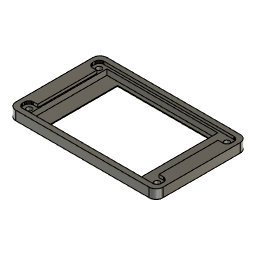
LCD_Skirt_Assembly (Autodesk Fusion 360 archive; units mm, degrees)
design "LCD_Face_Plate"
Autodesk Fusion 360 part; units mm, degrees
sketch "Adafruit PiTFT+ 3.2in-Edge_Cuts" plane through (0, 0, 0) normal (0, 0, 1) x (1, 0, 0)
  line L0 (-48.5948, 26.5683) -> (-48.3621, 27.006)
  line L1 (-48.5898, 23.3269) -> (-48.7364, 23.8005)
  line L2 (-48.74, 26.0892) -> (-48.5967, 26.5637)
  line L3 (-48.7365, 23.8008) -> (-48.7369, 23.803)
  line L4 (-48.3607, 27.0081) -> (-48.3594, 27.01)
  line L5 (-48.7894, 25.5898) -> (-48.7893, 25.591)
  line L6 (-48.7374, 23.8052) -> (-48.7892, 24.2983)
  line L7 (-48.7892, 24.2983) -> (-48.7892, 24.2986)
  line L8 (-48.0461, 27.3942) -> (-48.0461, 27.3942)
  line L9 (-46.7399, 28.1011) -> (-46.7378, 28.1016)
  line L10 (-47.2161, 27.954) -> (-46.7425, 28.1006)
  line L11 (46.7277, 28.1051) -> (46.73, 28.1046)
  line L12 (46.7274, 28.1051) -> (46.7277, 28.1051)
  line L13 (-46.2433, 28.1534) -> (-46.2422, 28.1535)
  line L14 (-46.2422, 28.1535) -> (-46.2257, 28.1536)
  line L15 (-47.6585, 27.7151) -> (-47.6566, 27.7163)
  line L16 (-48.3621, 27.006) -> (-48.3621, 27.006)
  line L17 (-47.6604, 27.7138) -> (-47.6585, 27.7151)
  line L18 (-48.7894, 24.3173) -> (-48.7894, 24.3174)
  line L19 (-46.7422, 28.1007) -> (-46.7399, 28.1011)
  line L20 (46.234, 28.1535) -> (46.7274, 28.1051)
  line L21 (-46.2257, 28.1536) -> (-46.2256, 28.1536)
  line L22 (-47.6607, 27.7136) -> (-47.6604, 27.7138)
  line L23 (47.2092, 27.9599) -> (47.2113, 27.959)
  line L24 (47.2071, 27.9608) -> (47.2092, 27.9599)
  line L25 (-46.7425, 28.1006) -> (-46.7425, 28.1006)
  line L26 (46.2328, 28.1536) -> (46.234, 28.1535)
  line L27 (-48.5966, 26.5641) -> (-48.5957, 26.5662)
  line L28 (46.7322, 28.1042) -> (47.2067, 27.9609)
  line L29 (-48.7409, 26.0847) -> (-48.7404, 26.087)
  line L30 (-48.0461, 27.3942) -> (-48.0459, 27.3944)
  line L31 (-48.7892, 24.2986) -> (-48.7892, 24.2997)
  line L32 (-48.3496, 22.8826) -> (-48.3509, 22.8845)
  line L33 (-48.3621, 27.006) -> (-48.3619, 27.0063)
  line L34 (-48.3594, 27.01) -> (-48.0461, 27.3942)
  line L35 (-48.7409, 26.0844) -> (-48.7409, 26.0847)
  line L36 (-47.2182, 27.9531) -> (-47.2161, 27.954)
  line L37 (-46.2447, 28.1534) -> (-46.2444, 28.1534)
  line L38 (-48.5957, 26.5662) -> (-48.5948, 26.5683)
  line L39 (-46.2444, 28.1534) -> (-46.2433, 28.1534)
  line L40 (-47.6566, 27.7163) -> (-47.2206, 27.9521)
  line L41 (-47.2206, 27.9521) -> (-47.2203, 27.9523)
  line L42 (-48.7364, 23.8005) -> (-48.7365, 23.8008)
  line L43 (-48.7893, 25.591) -> (-48.7893, 25.591)
  line L44 (-48.7893, 24.3008) -> (-48.7894, 24.3173)
  line L45 (-48.7893, 25.591) -> (-48.7409, 26.0844)
  line L46 (-48.3621, 27.006) -> (-48.3621, 27.006)
  line L47 (-48.0461, 27.3942) -> (-48.0461, 27.3942)
  line L48 (-47.2206, 27.9521) -> (-47.2206, 27.9521)
  line L49 (-46.7425, 28.1006) -> (-46.7422, 28.1007)
  line L50 (47.2067, 27.9609) -> (47.2071, 27.9608)
  line L51 (-46.7378, 28.1016) -> (-46.2447, 28.1534)
  line L52 (-48.5967, 26.5637) -> (-48.5966, 26.5641)
  line L53 (-48.3619, 27.0063) -> (-48.3607, 27.0081)
  line L54 (-48.0443, 27.396) -> (-48.0426, 27.3976)
  line L55 (46.73, 28.1046) -> (46.7322, 28.1042)
  line L56 (-48.0459, 27.3944) -> (-48.0443, 27.396)
  line L57 (-48.7369, 23.803) -> (-48.7374, 23.8052)
  line L58 (-48.7894, 24.3174) -> (-48.7894, 25.5898)
  line L59 (-47.6458, 22.1836) -> (-48.03, 22.4969)
  line L60 (-48.7404, 26.087) -> (-48.74, 26.0892)
  line L61 (-48.7892, 24.2997) -> (-48.7893, 24.3008)
  line L62 (48.6039, 23.3435) -> (48.6038, 23.3431)
  line L63 (48.0531, 22.5128) -> (48.0515, 22.5112)
  line L64 (46.7472, 21.8061) -> (46.745, 21.8056)
  line L65 (48.3593, 27.0208) -> (48.5951, 26.5848)
  line L66 (48.7481, 23.8225) -> (48.7476, 23.8202)
  line L67 (48.7964, 25.6089) -> (48.7964, 25.6086)
  line L68 (48.5961, 26.5824) -> (48.597, 26.5803)
  line L69 (46.234, 28.1535) -> (46.234, 28.1535)
  line L70 (48.3666, 22.8972) -> (48.0533, 22.513)
  line L71 (48.7964, 25.6086) -> (48.7964, 25.6075)
  line L72 (48.7472, 23.818) -> (48.6039, 23.3435)
  line L73 (48.3568, 27.0246) -> (48.3581, 27.0227)
  line L74 (48.7965, 25.6064) -> (48.7966, 25.5899)
  line L75 (47.649, 27.7263) -> (47.649, 27.7263)
  line L76 (48.5951, 26.5848) -> (48.5951, 26.5848)
  line L77 (48.7437, 26.1064) -> (48.7441, 26.1041)
  line L78 (48.602, 23.3389) -> (48.3693, 22.9012)
  line L79 (48.0515, 22.5112) -> (48.0498, 22.5096)
  line L80 (48.3691, 22.9009) -> (48.3678, 22.8991)
  line L81 (48.0372, 27.4103) -> (48.0372, 27.4103)
  line L82 (48.7436, 26.1067) -> (48.7437, 26.1064)
  line L83 (48.7446, 26.102) -> (48.7964, 25.6089)
  line L84 (48.039, 27.4085) -> (48.0406, 27.4068)
  line L85 (48.0372, 27.4103) -> (48.0372, 27.4103)
  line L86 (47.2113, 27.959) -> (47.6489, 27.7263)
  line L87 (-47.2206, 27.9521) -> (-47.2206, 27.9521)
  line L88 (48.7965, 24.3162) -> (48.7965, 24.3162)
  line L89 (47.2275, 21.9549) -> (47.2254, 21.9541)
  line L90 (48.7966, 25.5899) -> (48.7966, 25.5898)
  line L91 (48.5951, 26.5848) -> (48.5951, 26.5848)
  line L92 (48.3581, 27.0227) -> (48.3593, 27.0208)
  line L93 (48.6029, 23.341) -> (48.602, 23.3389)
  line L94 (48.0498, 22.5096) -> (47.6679, 22.1936)
  line L95 (-47.2203, 27.9523) -> (-47.2182, 27.9531)
  line L96 (48.0372, 27.4103) -> (48.0374, 27.4101)
  line L97 (48.3693, 22.9012) -> (48.3691, 22.9009)
  line L98 (48.5951, 26.5848) -> (48.5953, 26.5845)
  line L99 (47.6657, 22.1921) -> (47.6638, 22.1909)
  line L100 (47.6676, 22.1934) -> (47.6657, 22.1921)
  line L101 (47.2233, 21.9532) -> (46.7497, 21.8066)
  line L102 (48.7476, 23.8202) -> (48.7472, 23.818)
  line L103 (46.7497, 21.8066) -> (46.7494, 21.8065)
  line L104 (46.7494, 21.8065) -> (46.7472, 21.8061)
  line L105 (47.6679, 22.1936) -> (47.6676, 22.1934)
  line L106 (48.7966, 25.5898) -> (48.7966, 24.3174)
  line L107 (48.3678, 22.8991) -> (48.3666, 22.8972)
  line L108 (47.2254, 21.9541) -> (47.2233, 21.9532)
  line L109 (48.7441, 26.1041) -> (48.7446, 26.102)
  line L110 (48.597, 26.5803) -> (48.7436, 26.1067)
  line L111 (47.653, 27.7236) -> (48.0372, 27.4103)
  line L112 (-48.0426, 27.3976) -> (-47.6607, 27.7136)
  line L113 (47.6493, 27.7261) -> (47.6511, 27.7249)
  line L114 (47.649, 27.7263) -> (47.6493, 27.7261)
  line L115 (48.3566, 27.0249) -> (48.3568, 27.0246)
  line L116 (47.6511, 27.7249) -> (47.653, 27.7236)
  line L117 (48.0406, 27.4068) -> (48.3566, 27.0249)
  line L118 (46.745, 21.8056) -> (46.2519, 21.7538)
  line L119 (48.5953, 26.5845) -> (48.5961, 26.5824)
  line L120 (47.6489, 27.7263) -> (47.649, 27.7263)
  line L121 (48.0374, 27.4101) -> (48.039, 27.4085)
  line L122 (48.7964, 25.6075) -> (48.7965, 25.6064)
  line L123 (-46.2243, -21.8074) -> (-46.2408, -21.8075)
  line L124 (-46.2408, 28.1035) -> (-46.7301, 28.0521)
  line L125 (-47.9965, 22.5341) -> (-47.6161, 22.2239)
  line L126 (48.7966, 24.3174) -> (48.7965, 24.3162)
  line L127 (-47.199, 27.907) -> (-47.6307, 27.6735)
  line L128 (-48.6914, -23.8339) -> (-48.7394, -24.3236)
  line L129 (-48.5495, 26.5469) -> (-48.6914, 26.0771)
  line L130 (-42.5426, -21.8074) -> (-46.2243, -21.8074)
  line L131 (-42.5182, 21.7882) -> (-42.5168, 21.7835)
  line L132 (-47.6161, 22.2239) -> (-47.1827, 21.9935)
  line L133 (-42.5318, 21.8018) -> (-42.5274, 21.7995)
  line L134 (-42.5402, 21.8036) -> (-42.5365, 21.8032)
  line L135 (46.2516, 21.7538) -> (46.2505, 21.7538)
  line L136 (-48.7394, 24.3187) -> (-48.7393, 24.3022)
  line L137 (-47.6307, 27.6735) -> (-48.0089, 27.3607)
  line L138 (-48.6914, 26.0771) -> (-48.7394, 25.5874)
  line L139 (-42.5402, -21.8074) -> (-42.5414, -21.8075)
  line L140 (-42.5402, -21.8074) -> (-42.5402, -21.8074)
  line L141 (-42.5365, 21.8032) -> (-42.5318, 21.8018)
  line L142 (-42.5168, 21.7835) -> (-42.5163, 21.7786)
  line L143 (48.0533, 22.513) -> (48.0531, 22.5128)
  line L144 (-46.7301, -21.8589) -> (-47.199, -22.004)
  line L145 (-46.2243, 28.1036) -> (-46.2408, 28.1035)
  line L146 (-48.3191, -22.9307) -> (-48.5495, -23.3641)
  line L147 (46.2329, 21.7536) -> (46.2328, 21.7536)
  line L148 (-46.2232, 21.8036) -> (-42.5426, 21.8036)
  line L149 (-48.7393, 24.3022) -> (-48.6879, 23.8129)
  line L150 (-48.0089, -22.5503) -> (-48.3191, -22.9307)
  line L151 (42.4466, 21.7536) -> (42.4466, -21.7574)
  line L152 (-42.5205, -21.7964) -> (-42.5236, -21.8002)
  line L153 (48.7481, 23.8228) -> (48.7481, 23.8225)
  line L154 (-42.5365, -21.807) -> (-42.5402, -21.8074)
  line L155 (47.2278, 21.9551) -> (47.2275, 21.9549)
  line L156 (-42.5164, 21.7774) -> (-42.5164, -21.7812)
  line L157 (46.2328, 21.7536) -> (42.4466, 21.7536)
  line L158 (-47.1827, 21.9935) -> (-46.7129, 21.8516)
  line L159 (-42.5318, -21.8056) -> (-42.5365, -21.807)
  line L160 (-42.5274, 21.7995) -> (-42.5236, 21.7964)
  line L161 (48.6038, 23.3431) -> (48.6029, 23.341)
  line L162 (46.2494, 21.7537) -> (46.2329, 21.7536)
  line L163 (-48.3093, 22.9123) -> (-47.9965, 22.5341)
  line L164 (-42.5426, 21.8036) -> (-42.5414, 21.8037)
  line L165 (-42.5163, 21.7786) -> (-42.5164, 21.7774)
  line L166 (-42.5164, -21.7812) -> (-42.5163, -21.7824)
  line L167 (46.2519, 21.7538) -> (46.2516, 21.7538)
  line L168 (-47.6307, -22.2375) -> (-48.0089, -22.5503)
  line L169 (-42.5168, -21.7873) -> (-42.5182, -21.792)
  line L170 (-46.2408, -21.8075) -> (-46.7301, -21.8589)
  line L171 (-48.0089, 27.3607) -> (-48.3191, 26.9803)
  line L172 (46.2505, 21.7538) -> (46.2494, 21.7537)
  line L173 (-42.5163, -21.7824) -> (-42.5168, -21.7873)
  line L174 (-42.5236, -21.8002) -> (-42.5274, -21.8033)
  line L175 (-48.5428, 23.344) -> (-48.3093, 22.9123)
  line L176 (-42.5414, -21.8075) -> (-42.5426, -21.8074)
  line L177 (-48.6879, 23.8129) -> (-48.5428, 23.344)
  line L178 (-48.7394, 25.5874) -> (-48.7394, 24.3187)
  line L179 (-46.7301, 28.0521) -> (-47.199, 27.907)
  line L180 (-47.199, -22.004) -> (-47.6307, -22.2375)
  line L181 (-42.5414, 21.8037) -> (-42.5402, 21.8036)
  line L182 (47.6638, 22.1909) -> (47.2278, 21.9551)
  line L183 (-48.7394, -25.8463) -> (-48.7393, -25.8628)
  line L184 (48.7965, 24.3162) -> (48.7481, 23.8228)
  line L185 (-46.7129, 21.8516) -> (-46.2232, 21.8036)
  line L186 (-48.3191, 26.9803) -> (-48.5495, 26.5469)
  line L187 (46.248, 21.8037) -> (46.7373, 21.8551)
  line L188 (42.4204, -21.8074) -> (42.4167, -21.807)
  line L189 (48.7466, -25.8452) -> (48.7466, -24.3225)
  line L190 (-42.5274, -21.8033) -> (-42.5318, -21.8056)
  line L191 (48.3165, -22.9161) -> (48.0037, -22.5379)
  line L192 (42.4038, -21.8002) -> (42.4007, -21.7964)
  line L193 (-48.5428, -26.821) -> (-48.3093, -27.2527)
  line L194 (42.4038, 21.7964) -> (42.4076, 21.7995)
  line L195 (42.3966, 21.7774) -> (42.3965, 21.7786)
  line L196 (48.5567, -26.8047) -> (48.6986, -26.3349)
  line L197 (-48.6879, -26.3521) -> (-48.5428, -26.821)
  line L198 (46.2304, -21.8074) -> (42.4228, -21.8074)
  line L199 (-47.6161, -27.9411) -> (-47.1827, -28.1715)
  line L200 (42.4204, -21.8074) -> (42.4204, -21.8074)
  line L201 (46.248, -28.3613) -> (46.7373, -28.3099)
  line L202 (48.7465, -24.306) -> (48.6951, -23.8167)
  line L203 (48.55, -23.3478) -> (48.3165, -22.9161)
  line L204 (42.3966, -21.7812) -> (42.3966, 21.7774)
  line L205 (47.6379, -27.9313) -> (48.0161, -27.6185)
  line L206 (42.3965, 21.7786) -> (42.397, 21.7835)
  line L207 (-42.5236, 21.7964) -> (-42.5205, 21.7926)
  line L208 (42.4204, 21.8036) -> (42.4216, 21.8037)
  line L209 (47.2062, -28.1648) -> (47.6379, -27.9313)
  line L210 (42.3965, -21.7824) -> (42.3966, -21.7812)
  line L211 (48.7466, -24.3225) -> (48.7465, -24.306)
  line L212 (-42.5182, -21.792) -> (-42.5205, -21.7964)
  line L213 (-48.5495, -23.3641) -> (-48.6914, -23.8339)
  line L214 (46.2315, -28.3614) -> (46.248, -28.3613)
  line L215 (-46.2232, -28.3614) -> (46.2315, -28.3614)
  line L216 (42.4076, 21.7995) -> (42.412, 21.8018)
  line L217 (-42.5205, 21.7926) -> (-42.5182, 21.7882)
  line L218 (42.397, 21.7835) -> (42.3984, 21.7882)
  line L219 (-48.7393, -25.8628) -> (-48.6879, -26.3521)
  line L220 (42.4167, -21.807) -> (42.412, -21.8056)
  line L221 (46.7373, -28.3099) -> (47.2062, -28.1648)
  line L222 (48.3263, -27.2381) -> (48.5567, -26.8047)
  line L223 (42.3984, 21.7882) -> (42.4007, 21.7926)
  line L224 (42.412, 21.8018) -> (42.4167, 21.8032)
  line L225 (47.6233, -22.2277) -> (47.1899, -21.9973)
  line L226 (46.7201, -21.8554) -> (46.2304, -21.8074)
  line L227 (48.0161, -27.6185) -> (48.3263, -27.2381)
  line L228 (42.4076, -21.8033) -> (42.4038, -21.8002)
  line L229 (42.4007, 21.7926) -> (42.4038, 21.7964)
  line L230 (42.4167, 21.8032) -> (42.4204, 21.8036)
  line L231 (-47.9965, -27.6309) -> (-47.6161, -27.9411)
  line L232 (42.4216, 21.8037) -> (42.4228, 21.8036)
  line L233 (42.4228, 21.8036) -> (46.2315, 21.8036)
  line L234 (42.397, -21.7873) -> (42.3965, -21.7824)
  line L235 (-46.7129, -28.3134) -> (-46.2232, -28.3614)
  line L236 (-48.3093, -27.2527) -> (-47.9965, -27.6309)
  line L237 (46.2315, 21.8036) -> (46.248, 21.8037)
  line L238 (48.0037, -22.5379) -> (47.6233, -22.2277)
  line L239 (42.4216, -21.8075) -> (42.4204, -21.8074)
  line L240 (42.4228, -21.8074) -> (42.4216, -21.8075)
  line L241 (48.6986, -26.3349) -> (48.7466, -25.8452)
  line L242 (42.3984, -21.792) -> (42.397, -21.7873)
  line L243 (-47.1827, -28.1715) -> (-46.7129, -28.3134)
  line L244 (-48.7394, -24.3236) -> (-48.7394, -25.8463)
  line L245 (42.4007, -21.7964) -> (42.3984, -21.792)
  line L246 (48.6951, -23.8167) -> (48.55, -23.3478)
  line L247 (42.412, -21.8056) -> (42.4076, -21.8033)
  line L248 (47.1899, -21.9973) -> (46.7201, -21.8554)
  line L249 (48.7466, 25.5885) -> (48.7465, 25.605)
  line L250 (47.1899, 27.9137) -> (46.7201, 28.0556)
  line L251 (47.2062, 22.0002) -> (47.6379, 22.2337)
  line L252 (48.55, 26.5632) -> (48.3165, 26.9949)
  line L253 (48.6986, 23.8301) -> (48.7466, 24.3198)
  line L254 (48.6951, 26.0943) -> (48.55, 26.5632)
  line L255 (46.7373, 21.8551) -> (47.2062, 22.0002)
  line L256 (47.6379, 22.2337) -> (48.0161, 22.5465)
  line L257 (48.7465, 25.605) -> (48.6951, 26.0943)
  line L258 (48.0037, 27.3731) -> (47.6233, 27.6833)
  line L259 (47.6233, 27.6833) -> (47.1899, 27.9137)
  line L260 (46.7201, 28.0556) -> (46.2304, 28.1036)
  line L261 (48.7466, 24.3198) -> (48.7466, 25.5885)
  line L262 (46.2304, 28.1036) -> (-46.2243, 28.1036)
  line L263 (48.5567, 23.3603) -> (48.6986, 23.8301)
  line L264 (48.3165, 26.9949) -> (48.0037, 27.3731)
  line L265 (48.0161, 22.5465) -> (48.3263, 22.9269)
  line L266 (48.3263, 22.9269) -> (48.5567, 23.3603)
  line L267 (47.6511, -22.1861) -> (47.653, -22.1874)
  line L268 (48.3581, -22.8883) -> (48.3593, -22.8902)
  line L269 (48.5951, -23.3262) -> (48.5953, -23.3265)
  line L270 (48.5951, -23.3262) -> (48.5951, -23.3262)
  line L271 (47.2113, -21.952) -> (47.6489, -22.1847)
  line L272 (48.3593, -22.8902) -> (48.5951, -23.3262)
  line L273 (46.234, -21.7575) -> (46.7274, -21.8059)
  line L274 (48.039, -22.5025) -> (48.0406, -22.5042)
  line L275 (47.6489, -22.1847) -> (47.649, -22.1847)
  line L276 (47.2092, -21.9511) -> (47.2113, -21.952)
  line L277 (46.7277, -21.8059) -> (46.73, -21.8064)
  line L278 (48.0372, -22.5007) -> (48.0374, -22.5009)
  line L279 (46.73, -21.8064) -> (46.7322, -21.8068)
  line L280 (46.234, -21.7575) -> (46.234, -21.7575)
  line L281 (48.5951, -23.3262) -> (48.5951, -23.3262)
  line L282 (42.4466, -21.7574) -> (46.2328, -21.7574)
  line L283 (47.653, -22.1874) -> (48.0372, -22.5007)
  line L284 (48.0515, -27.6538) -> (48.0498, -27.6554)
  line L285 (48.3691, -27.2641) -> (48.3678, -27.2659)
  line L286 (48.0372, -22.5007) -> (48.0372, -22.5007)
  line L287 (48.7964, -24.3021) -> (48.7964, -24.3024)
  line L288 (48.7964, -24.3035) -> (48.7965, -24.3046)
  line L289 (48.7965, -25.8488) -> (48.7965, -25.8488)
  line L290 (48.7472, -26.347) -> (48.6039, -26.8215)
  line L291 (48.7966, -24.3212) -> (48.7966, -25.8476)
  line L292 (-47.2041, -28.2168) -> (-47.6418, -27.9841)
  line L293 (48.0372, -22.5007) -> (48.0372, -22.5007)
  line L294 (-46.2256, -28.4114) -> (-46.2268, -28.4113)
  line L295 (-47.6418, -27.9841) -> (-47.6421, -27.9839)
  line L296 (48.7481, -26.3422) -> (48.7481, -26.3425)
  line L297 (-47.6439, -27.9826) -> (-47.6458, -27.9814)
  line L298 (46.2516, -28.4112) -> (46.2505, -28.4112)
  line L299 (-47.202, -28.2177) -> (-47.2041, -28.2168)
  line L300 (48.6039, -26.8215) -> (48.6038, -26.8219)
  line L301 (-47.6421, -27.9839) -> (-47.6439, -27.9826)
  line L302 (47.2275, -28.2101) -> (47.2254, -28.2109)
  line L303 (48.3666, -27.2678) -> (48.0533, -27.652)
  line L304 (46.2519, -28.4112) -> (46.2516, -28.4112)
  line L305 (46.7274, -21.8059) -> (46.7277, -21.8059)
  line L306 (46.2505, -28.4112) -> (46.2494, -28.4113)
  line L307 (47.2233, -28.2118) -> (46.7497, -28.3584)
  line L308 (47.2278, -28.2099) -> (47.2275, -28.2101)
  line L309 (47.6493, -22.1849) -> (47.6511, -22.1861)
  line L310 (48.602, -26.8261) -> (48.3693, -27.2638)
  line L311 (46.7497, -28.3584) -> (46.7494, -28.3585)
  line L312 (48.3693, -27.2638) -> (48.3691, -27.2641)
  line L313 (47.6679, -27.9714) -> (47.6676, -27.9716)
  line L314 (48.7441, -23.8069) -> (48.7446, -23.809)
  line L315 (48.7966, -25.8476) -> (48.7965, -25.8488)
  line L316 (47.649, -22.1847) -> (47.6493, -22.1849)
  line L317 (48.0374, -22.5009) -> (48.039, -22.5025)
  line L318 (48.3568, -22.8864) -> (48.3581, -22.8883)
  line L319 (46.7322, -21.8068) -> (47.2067, -21.9501)
  line L320 (48.5953, -23.3265) -> (48.5961, -23.3286)
  line L321 (48.6029, -26.824) -> (48.602, -26.8261)
  line L322 (48.3566, -22.8861) -> (48.3568, -22.8864)
  line L323 (48.7966, -24.3211) -> (48.7966, -24.3212)
  line L324 (48.0531, -27.6522) -> (48.0515, -27.6538)
  line L325 (48.7964, -24.3024) -> (48.7964, -24.3035)
  line L326 (46.2328, -21.7574) -> (46.234, -21.7575)
  line L327 (48.7476, -26.3448) -> (48.7472, -26.347)
  line L328 (48.7965, -24.3046) -> (48.7966, -24.3211)
  line L329 (48.0498, -27.6554) -> (47.6679, -27.9714)
  line L330 (48.0533, -27.652) -> (48.0531, -27.6522)
  line L331 (48.597, -23.3307) -> (48.7436, -23.8043)
  line L332 (47.2067, -21.9501) -> (47.2071, -21.9502)
  line L333 (48.5961, -23.3286) -> (48.597, -23.3307)
  line L334 (48.7481, -26.3425) -> (48.7476, -26.3448)
  line L335 (47.649, -22.1847) -> (47.649, -22.1847)
  line L336 (48.6038, -26.8219) -> (48.6029, -26.824)
  line L337 (48.7436, -23.8043) -> (48.7437, -23.8046)
  line L338 (48.7965, -25.8488) -> (48.7481, -26.3422)
  line L339 (47.2071, -21.9502) -> (47.2092, -21.9511)
  line L340 (48.7437, -23.8046) -> (48.7441, -23.8069)
  line L341 (48.3678, -27.2659) -> (48.3666, -27.2678)
  line L342 (48.0406, -22.5042) -> (48.3566, -22.8861)
  line L343 (48.7446, -23.809) -> (48.7964, -24.3021)
  line L344 (-48.7893, -24.32) -> (-48.7409, -23.8266)
  line L345 (-48.03, -27.6681) -> (-48.0302, -27.6679)
  line L346 (-48.7409, -23.8266) -> (-48.7409, -23.8263)
  line L347 (-48.3594, -22.901) -> (-48.0461, -22.5168)
  line L348 (-48.7892, -25.8653) -> (-48.7893, -25.8642)
  line L349 (-48.0426, -22.5134) -> (-47.6607, -22.1974)
  line L350 (46.745, -28.3594) -> (46.2519, -28.4112)
  line L351 (-47.1999, -28.2186) -> (-47.202, -28.2177)
  line L352 (-47.1995, -28.2187) -> (-47.1999, -28.2186)
  line L353 (-48.3494, -27.2827) -> (-48.3496, -27.2824)
  line L354 (46.7472, -28.3589) -> (46.745, -28.3594)
  line L355 (-46.725, -28.362) -> (-47.1995, -28.2187)
  line L356 (46.2494, -28.4113) -> (46.2329, -28.4114)
  line L357 (-46.2268, -28.4113) -> (-46.7202, -28.3629)
  line L358 (47.6676, -27.9716) -> (47.6657, -27.9729)
  line L359 (-48.5967, -23.3473) -> (-48.5966, -23.3469)
  line L360 (-48.7365, -26.3642) -> (-48.7369, -26.362)
  line L361 (-48.7892, -25.8667) -> (-48.7892, -25.8664)
  line L362 (-48.7893, -25.8642) -> (-48.7894, -25.8477)
  line L363 (46.2328, -28.4114) -> (-46.2256, -28.4114)
  line L364 (-46.2268, -28.4113) -> (-46.2268, -28.4113)
  line L365 (-48.5881, -26.8423) -> (-48.5889, -26.8402)
  line L366 (-48.5889, -26.8402) -> (-48.5898, -26.8381)
  line L367 (-46.7228, -28.3624) -> (-46.725, -28.362)
  line L368 (-48.5879, -26.8426) -> (-48.5881, -26.8423)
  line L369 (-48.5966, -23.3469) -> (-48.5957, -23.3448)
  line L370 (-48.3496, -27.2824) -> (-48.3509, -27.2805)
  line L371 (-48.7894, -24.3212) -> (-48.7893, -24.32)
  line L372 (46.2329, -28.4114) -> (46.2328, -28.4114)
  line L373 (-48.0334, -27.6646) -> (-48.3494, -27.2827)
  line L374 (-48.0461, -22.5168) -> (-48.0461, -22.5168)
  line L375 (-47.6607, -22.1974) -> (-47.6604, -22.1972)
  line L376 (47.6657, -27.9729) -> (47.6638, -27.9741)
  line L377 (-48.3521, -27.2786) -> (-48.5879, -26.8426)
  line L378 (-48.5898, -26.8381) -> (-48.7364, -26.3645)
  line L379 (-48.7892, -25.8664) -> (-48.7892, -25.8653)
  line L380 (-48.7894, -25.8476) -> (-48.7894, -24.3212)
  line L381 (-48.0461, -22.5168) -> (-48.0459, -22.5166)
  line L382 (-48.0443, -22.515) -> (-48.0426, -22.5134)
  line L383 (-47.2206, -21.9589) -> (-47.2206, -21.9589)
  line L384 (-48.3621, -22.905) -> (-48.3621, -22.905)
  line L385 (-47.6458, -27.9814) -> (-48.03, -27.6681)
  line L386 (-48.3607, -22.9029) -> (-48.3594, -22.901)
  line L387 (-48.7374, -26.3598) -> (-48.7892, -25.8667)
  line L388 (-48.7893, -24.32) -> (-48.7893, -24.32)
  line L389 (-48.0302, -27.6679) -> (-48.0318, -27.6663)
  line L390 (-46.7205, -28.3629) -> (-46.7228, -28.3624)
  line L391 (-48.0318, -27.6663) -> (-48.0334, -27.6646)
  line L392 (-46.7202, -28.3629) -> (-46.7205, -28.3629)
  line L393 (-48.7404, -23.824) -> (-48.74, -23.8218)
  line L394 (47.2254, -28.2109) -> (47.2233, -28.2118)
  line L395 (-48.74, -23.8218) -> (-48.5967, -23.3473)
  line L396 (47.6638, -27.9741) -> (47.2278, -28.2099)
  line L397 (-48.7409, -23.8263) -> (-48.7404, -23.824)
  line L398 (-48.7369, -26.362) -> (-48.7374, -26.3598)
  line L399 (-48.7364, -26.3645) -> (-48.7365, -26.3642)
  line L400 (-48.7894, -25.8477) -> (-48.7894, -25.8476)
  line L401 (-48.3509, -27.2805) -> (-48.3521, -27.2786)
  line L402 (46.7494, -28.3585) -> (46.7472, -28.3589)
  line L403 (-47.2203, -21.9587) -> (-47.2182, -21.9579)
  line L404 (-48.3621, -22.905) -> (-48.3619, -22.9047)
  line L405 (-48.5948, -23.3427) -> (-48.3621, -22.905)
  line L406 (-46.2268, 21.7537) -> (-46.7202, 21.8021)
  line L407 (-46.7378, -21.8094) -> (-46.2447, -21.7576)
  line L408 (-47.202, 21.9473) -> (-47.2041, 21.9482)
  line L409 (-46.2256, -21.7574) -> (-42.5664, -21.7574)
  line L410 (-47.2041, 21.9482) -> (-47.6418, 22.1809)
  line L411 (-48.3494, 22.8823) -> (-48.3496, 22.8826)
  line L412 (-48.5879, 23.3224) -> (-48.5881, 23.3227)
  line L413 (-46.2422, -21.7575) -> (-46.2257, -21.7574)
  line L414 (-47.6439, 22.1824) -> (-47.6458, 22.1836)
  line L415 (-47.1995, 21.9463) -> (-47.1999, 21.9464)
  line L416 (-42.5664, 21.7536) -> (-46.2256, 21.7536)
  line L417 (-46.7399, -21.8099) -> (-46.7378, -21.8094)
  line L418 (-48.03, 22.4969) -> (-48.0302, 22.4971)
  line L419 (-48.5957, -23.3448) -> (-48.5948, -23.3427)
  line L420 (-46.7425, -21.8104) -> (-46.7422, -21.8103)
  line L421 (-47.6604, -22.1972) -> (-47.6585, -22.1959)
  line L422 (-48.0461, -22.5168) -> (-48.0461, -22.5168)
  line L423 (-46.725, 21.803) -> (-47.1995, 21.9463)
  line L424 (-46.2257, -21.7574) -> (-46.2256, -21.7574)
  line L425 (-47.6418, 22.1809) -> (-47.6421, 22.1811)
  line L426 (-46.2256, 21.7536) -> (-46.2268, 21.7537)
  line L427 (-46.2447, -21.7576) -> (-46.2444, -21.7576)
  line L428 (-47.2182, -21.9579) -> (-47.2161, -21.957)
  line L429 (-46.7228, 21.8026) -> (-46.725, 21.803)
  line L430 (-47.1999, 21.9464) -> (-47.202, 21.9473)
  line L431 (-47.2206, -21.9589) -> (-47.2203, -21.9587)
  line L432 (-47.2206, -21.9589) -> (-47.2206, -21.9589)
  line L433 (-46.7205, 21.8021) -> (-46.7228, 21.8026)
  line L434 (-48.0302, 22.4971) -> (-48.0318, 22.4987)
  line L435 (-46.2268, 21.7537) -> (-46.2268, 21.7537)
  line L436 (-42.5664, -21.7574) -> (-42.5664, 21.7536)
  line L437 (-48.3521, 22.8864) -> (-48.5879, 23.3224)
  line L438 (-46.7202, 21.8021) -> (-46.7205, 21.8021)
  line L439 (-46.7422, -21.8103) -> (-46.7399, -21.8099)
  line L440 (-47.6421, 22.1811) -> (-47.6439, 22.1824)
  line L441 (-46.2433, -21.7576) -> (-46.2422, -21.7575)
  line L442 (-47.2161, -21.957) -> (-46.7425, -21.8104)
  line L443 (-46.7425, -21.8104) -> (-46.7425, -21.8104)
  line L444 (-48.3619, -22.9047) -> (-48.3607, -22.9029)
  line L445 (-46.2444, -21.7576) -> (-46.2433, -21.7576)
  line L446 (-48.3509, 22.8845) -> (-48.3521, 22.8864)
  line L447 (-48.3621, -22.905) -> (-48.3621, -22.905)
  line L448 (-47.6566, -22.1947) -> (-47.2206, -21.9589)
  line L449 (-48.5881, 23.3227) -> (-48.5889, 23.3248)
  line L450 (-48.0459, -22.5166) -> (-48.0443, -22.515)
  line L451 (-48.0318, 22.4987) -> (-48.0334, 22.5004)
  line L452 (-47.6585, -22.1959) -> (-47.6566, -22.1947)
  line L453 (-48.5889, 23.3248) -> (-48.5898, 23.3269)
  line L454 (-48.0334, 22.5004) -> (-48.3494, 22.8823)
  line L455 (43.1466, -21.0574) -> (43.1466, 21.0536)
  line L456 (43.1466, 21.0536) -> (46.2338, 21.0536)
  line L457 (46.2338, 21.0536) -> (46.2896, 21.0539)
  line L458 (46.2896, 21.0539) -> (46.8888, 21.1169)
  line L459 (46.8888, 21.1169) -> (47.4983, 21.3055)
  line L460 (47.4983, 21.3055) -> (48.0593, 21.609)
  line L461 (48.0593, 21.609) -> (48.5508, 22.0155)
  line L462 (48.5508, 22.0155) -> (48.954, 22.5099)
  line L463 (48.954, 22.5099) -> (49.2534, 23.0731)
  line L464 (49.2534, 23.0731) -> (49.4378, 23.6837)
  line L465 (49.4378, 23.6837) -> (49.4966, 24.2831)
  line L466 (49.4966, 24.2831) -> (49.4966, 25.5908)
  line L467 (49.4966, 25.5908) -> (49.4963, 25.6466)
  line L468 (49.4963, 25.6466) -> (49.4333, 26.2458)
  line L469 (49.4333, 26.2458) -> (49.2447, 26.8553)
  line L470 (49.2447, 26.8553) -> (48.9412, 27.4163)
  line L471 (48.9412, 27.4163) -> (48.5347, 27.9078)
  line L472 (48.5347, 27.9078) -> (48.0403, 28.311)
  line L473 (48.0403, 28.311) -> (47.4771, 28.6104)
  line L474 (47.4771, 28.6104) -> (46.8665, 28.7948)
  line L475 (46.8665, 28.7948) -> (46.2671, 28.8536)
  line L476 (46.2671, 28.8536) -> (-46.2266, 28.8536)
  line L477 (-46.2266, 28.8536) -> (-46.2824, 28.8533)
  line L478 (-46.2824, 28.8533) -> (-46.8816, 28.7903)
  line L479 (-46.8816, 28.7903) -> (-47.4911, 28.6017)
  line L480 (-47.4911, 28.6017) -> (-48.0521, 28.2982)
  line L481 (-48.0521, 28.2982) -> (-48.5436, 27.8917)
  line L482 (-48.5436, 27.8917) -> (-48.9468, 27.3973)
  line L483 (-48.9468, 27.3973) -> (-49.2462, 26.8341)
  line L484 (-49.2462, 26.8341) -> (-49.4306, 26.2235)
  line L485 (-49.4306, 26.2235) -> (-49.4894, 25.6241)
  line L486 (-49.4894, 25.6241) -> (-49.4894, 24.3164)
  line L487 (-49.4894, 24.3164) -> (-49.4891, 24.2606)
  line L488 (-49.4891, 24.2606) -> (-49.4261, 23.6614)
  line L489 (-49.4261, 23.6614) -> (-49.2375, 23.0519)
  line L490 (-49.2375, 23.0519) -> (-48.934, 22.4909)
  line L491 (-48.934, 22.4909) -> (-48.5275, 21.9994)
  line L492 (-48.5275, 21.9994) -> (-48.0331, 21.5962)
  line L493 (-48.0331, 21.5962) -> (-47.4699, 21.2968)
  line L494 (-47.4699, 21.2968) -> (-46.8593, 21.1124)
  line L495 (-46.8593, 21.1124) -> (-46.2599, 21.0536)
  line L496 (-46.2599, 21.0536) -> (-43.2664, 21.0536)
  line L497 (-43.2664, 21.0536) -> (-43.2664, -21.0574)
  line L498 (-43.2664, -21.0574) -> (-46.2266, -21.0574)
  line L499 (-46.2266, -21.0574) -> (-46.2824, -21.0577)
  line L500 (-46.2824, -21.0577) -> (-46.8816, -21.1207)
  line L501 (-46.8816, -21.1207) -> (-47.4911, -21.3093)
  line L502 (-47.4911, -21.3093) -> (-48.0521, -21.6128)
  line L503 (-48.0521, -21.6128) -> (-48.5436, -22.0193)
  line L504 (-48.5436, -22.0193) -> (-48.9468, -22.5137)
  line L505 (-48.9468, -22.5137) -> (-49.2462, -23.0769)
  line L506 (-49.2462, -23.0769) -> (-49.4306, -23.6875)
  line L507 (-49.4306, -23.6875) -> (-49.4894, -24.2869)
  line L508 (-49.4894, -24.2869) -> (-49.4894, -25.8486)
  line L509 (-49.4894, -25.8486) -> (-49.4891, -25.9044)
  line L510 (-49.4891, -25.9044) -> (-49.4261, -26.5036)
  line L511 (-49.4261, -26.5036) -> (-49.2375, -27.1131)
  line L512 (-49.2375, -27.1131) -> (-48.934, -27.6741)
  line L513 (-48.934, -27.6741) -> (-48.5275, -28.1656)
  line L514 (-48.5275, -28.1656) -> (-48.0331, -28.5688)
  line L515 (-48.0331, -28.5688) -> (-47.4699, -28.8682)
  line L516 (-47.4699, -28.8682) -> (-46.8593, -29.0526)
  line L517 (-46.8593, -29.0526) -> (-46.2599, -29.1114)
  line L518 (-46.2599, -29.1114) -> (46.2338, -29.1114)
  line L519 (46.2338, -29.1114) -> (46.2896, -29.1111)
  line L520 (46.2896, -29.1111) -> (46.8888, -29.0481)
  line L521 (46.8888, -29.0481) -> (47.4983, -28.8595)
  line L522 (47.4983, -28.8595) -> (48.0593, -28.556)
  line L523 (48.0593, -28.556) -> (48.5508, -28.1495)
  line L524 (48.5508, -28.1495) -> (48.954, -27.6551)
  line L525 (48.954, -27.6551) -> (49.2534, -27.0919)
  line L526 (49.2534, -27.0919) -> (49.4378, -26.4813)
  line L527 (49.4378, -26.4813) -> (49.4966, -25.8819)
  line L528 (49.4966, -25.8819) -> (49.4966, -24.3202)
  line L529 (49.4966, -24.3202) -> (49.4963, -24.2644)
  line L530 (49.4963, -24.2644) -> (49.4333, -23.6652)
  line L531 (49.4333, -23.6652) -> (49.2447, -23.0557)
  line L532 (49.2447, -23.0557) -> (48.9412, -22.4947)
  line L533 (48.9412, -22.4947) -> (48.5347, -22.0032)
  line L534 (48.5347, -22.0032) -> (48.0403, -21.6)
  line L535 (48.0403, -21.6) -> (47.4771, -21.3006)
  line L536 (47.4771, -21.3006) -> (46.8665, -21.1162)
  line L537 (46.8665, -21.1162) -> (46.2671, -21.0574)
  line L538 (46.2671, -21.0574) -> (43.1466, -21.0574)
  line L539 (-42.5168, 21.7835) -> (-42.5168, 28.1036) construction
  line L540 (-42.5168, 24.9436) -> (-45.5168, 24.9436) construction
  circle A0 centre (-45.5168, 24.9436) radius 1.875
  line L541 (0, 0) -> (0.0202, 28.8536) construction
  line L542 (0, 0) -> (-43.2664, -0.0019) construction
  circle A1 centre (-45.5146, -24.9475) radius 1.875
  circle A2 centre (45.4795, -25.0114) radius 1.875
  circle A3 centre (45.5518, 24.8796) radius 1.875
  line L543 (52.5, 32.5) -> (-52.5, 32.5)
  line L544 (-52.5, 32.5) -> (-52.5, -32.5)
  line L545 (-52.5, -32.5) -> (52.5, -32.5)
  line L546 (52.5, -32.5) -> (52.5, 32.5)
  line L547 (52.5, 32.5) -> (-52.5, -32.5) construction
  line L548 (-52.5, 32.5) -> (52.5, -32.5) construction
  dimension "d1" = 0.75
  dimension "d2" = 3
  dimension "d3" = 3.75
  dimension "d4" = 65
  dimension "d5" = 105
  constraint coincident L262 L539.end
  constraint perpendicular L262 L539
  constraint midpoint L539 L540.start
  constraint perpendicular L539 L540
  constraint coincident L540.end A0.centre
  constraint coincident L541.start L542.start
  constraint midpoint L476 L541.end
  constraint midpoint L497 L542.end
  constraint symmetric A0 L542 A1
  constraint symmetric A0 L541 A3
  constraint symmetric L541 A1 A2
  constraint horizontal L543
  constraint perpendicular L543 L544
  constraint parallel L543 L545
  constraint parallel L544 L546
  constraint coincident L547 L541.start
  constraint coincident L548 L541.start
  measures "d2" distance of L540.start L540.end
  measures "d3" diameter of A0
  measures "d4" distance of L543.start L545.end
  measures "d5" distance of L544.end L545.end
sketch "Sketch2" plane through (0, 0, 0) normal (0, 0, 1) x (1, 0, 0)
  line L0 (-42.5164, 21.7774) -> (-42.5164, -21.7812)
  line L1 (-42.5164, -27.5) -> (36.4836, -27.5)
  line L2 (36.4836, -27.5) -> (36.4836, 27.5)
  line L3 (36.4836, 27.5) -> (-42.5164, 27.5)
  line L4 (-42.5164, 27.5) -> (-42.5164, -27.5)
  line L5 (-42.5164, -27.5) -> (36.4836, 27.5) construction
  line L6 (36.4836, -27.5) -> (-42.5164, 27.5) construction
  line L7 (-3.0164, 0) -> (0, 0) construction
  line L8 (32.5, 25) -> (-32.5, 25)
  line L9 (-32.5, 25) -> (-32.5, -25)
  line L10 (-32.5, -25) -> (32.5, -25)
  line L11 (32.5, -25) -> (32.5, 25)
  line L12 (32.5, 25) -> (-32.5, -25) construction
  line L13 (-32.5, 25) -> (32.5, -25) construction
  point P0 (-3.0164, 0)
  dimension "d6" = 79
  dimension "d7" = 55
  dimension "d8" = 50
  dimension "d9" = 65
  constraint horizontal L1
  constraint perpendicular L1 L2
  constraint parallel L1 L3
  constraint parallel L2 L4
  constraint coincident L0 L1.start
  constraint coincident L5 P0
  constraint coincident L6 P0
  constraint coincident P0 L7.start
  constraint coincident L7.end origin
  constraint horizontal L7
  constraint horizontal L8
  constraint perpendicular L8 L9
  constraint parallel L8 L10
  constraint parallel L9 L11
  constraint coincident L12 L7.end
  constraint coincident L13 L7.end
  measures "d6" distance of L2.end L3.end
  measures "d7" distance of L1.end L2.end
  measures "d8" distance of L8.start L10.end
  measures "d9" distance of L8.start L8.end
extrude "Extrude3" add sketch "Sketch2" sketch "Adafruit PiTFT+ 3.2in-Edge_Cuts" along normal blind 7 contours L0 L1 L2 L3 L4 | L8 L9 L10 L11 of sketch 2 contours L123 L124 L125 L127 L128 L129 L130 L131 L132 L133 L134 L136 L137 L138 L139 L141 L142 L144 L145 L146 L148 L149 L150 L152 L154 L156 L158 L159 L160 L163 L164 L168 L169 L170 L171 L173 L174 L175 L177 L178 L179 L180 L183 L185 L186 L187 L188 L189 L190 L191 L192 L193 L194 L196 L197 L198 L199 L201 L202 L203 L204 L205 L206 L207 L209 L211 L212 L213 L214 L215 L216 L217 L218 L219 L220 L221 L222 L223 L224 L225 L226 L227 L228 L229 L230 L231 L232 L233 L234 L235 L236 L237 L238 L240 L241 L242 L243 L244 L245 L246 L247 L248 L249 L250 L251 L252 L253 L254 L255 L256 L257 L258 L259 L260 L261 L262 L263 L264 L265 L266 | L455 L456 L457 L458 L459 L460 L461 L462 L463 L464 L465 L466 L467 L468 L469 L470 L471 L472 L473 L474 L475 L476 L477 L478 L479 L480 L481 L482 L483 L484 L485 L486 L487 L488 L489 L490 L491 L492 L493 L494 L495 L496 L497 L498 L499 L500 L501 L502 L503 L504 L505 L506 L507 L508 L509 L510 L511 L512 L513 L514 L515 L516 L517 L518 L519 L520 L521 L522 L523 L524 L525 L526 L527 L528 L529 L530 L531 L532 L533 L534 L535 L536 L537 L538 | L543 L544 L545 L546
extrude "Extrude4" cut sketch "Sketch2" along normal through all and the other way through all contours L8 L9 L10 L11
extrude "Extrude5" cut sketch "Adafruit PiTFT+ 3.2in-Edge_Cuts" along normal blind 2 contours L123 L124 L125 L127 L128 L129 L130 L131 L132 L133 L134 L136 L137 L138 L139 L141 L142 L144 L145 L146 L148 L149 L150 L152 L154 L156 L158 L159 L160 L163 L164 L168 L169 L170 L171 L173 L174 L175 L177 L178 L179 L180 L183 L185 L186 L187 L188 L189 L190 L191 L192 L193 L194 L196 L197 L198 L199 L201 L202 L203 L204 L205 L206 L207 L209 L211 L212 L213 L214 L215 L216 L217 L218 L219 L220 L221 L222 L223 L224 L225 L226 L227 L228 L229 L230 L231 L232 L233 L234 L235 L236 L237 L238 L240 L241 L242 L243 L244 L245 L246 L247 L248 L249 L250 L251 L252 L253 L254 L255 L256 L257 L258 L259 L260 L261 L262 L263 L264 L265 L266 | L455 L456 L457 L458 L459 L460 L461 L462 L463 L464 L465 L466 L467 L468 L469 L470 L471 L472 L473 L474 L475 L476 L477 L478 L479 L480 L481 L482 L483 L484 L485 L486 L487 L488 L489 L490 L491 L492 L493 L494 L495 L496 L497 L498 L499 L500 L501 L502 L503 L504 L505 L506 L507 L508 L509 L510 L511 L512 L513 L514 L515 L516 L517 L518 L519 L520 L521 L522 L523 L524 L525 L526 L527 L528 L529 L530 L531 L532 L533 L534 L535 L536 L537 L538
extrude "Extrude6" cut sketch "Sketch2" along normal blind 6
fillet "Fillet1" radius 5 4 edges at (-52.5, -32.5, 3.5) (52.5, -32.5, 3.5) (52.5, 32.5, 3.5) (-52.5, 32.5, 3.5)
move_body "Move1" bodies 1 to x (1, 0, 0) y (0, -1, 0) z (0, 0, -1) at (0, 0, 0)
chamfer "Chamfer1" distance 0.5 angle 45 8 edges at (52.5, 0, -7) (51.0355, -31.0355, -7) (0, -32.5, -7) (-51.0355, -31.0355, -7) (-52.5, 0, -7) (-51.0355, 31.0355, -7) (0, 32.5, -7) (51.0355, 31.0355, -7) 1 faces at (36.6222, -7.7114, -7)
